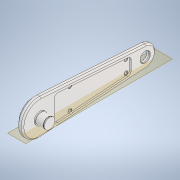
# Autodesk Inventor part: 1.3_2_SideArmClose
Saved by Autodesk Inventor 2021 (Build 250183000, 183)
## iProperties
Created: 2025-11-12
Part Number: 1.3_2_SideArmClose
Material: ABS Plastic
Document SubType Name: Modeling
Designer: Admin
Density: 1.06 g/cm^3
Appearance: Smooth - White
Mass: 286.641 g
Surface Area: 768.971 cm^2
Volume: 270.416 cm^3
Author: Admin
Title: Side Arm Closure (3rd)
Autodesk Inventor part; units mm, degrees
ref_plane "YZ Plane" through (0, 0, 0) normal (1, 0, 0) x (0, 1, 0)
ref_plane "XY Plane" through (0, 0, 0) normal (0, 0, 1) x (1, 0, 0)
sketch "Sketch1" plane through (0, 0, 0) normal (1, 0, 0) x (0, 1, 0)
  circle A0 centre (0, 0) radius 50
  circle A1 centre (0, -300) radius 30
  line L0 (0, 0) -> (0, -300) construction
  line L1 (49.8888, -3.3333) -> (29.9333, -302)
  line L2 (-49.8888, -3.3333) -> (-29.9333, -302)
  dimension "d0" = 300
  dimension "d1" = 100
  dimension "d2" = 60
  constraints: 6 end point, 4 point on circle, 3 tangent, 2 centre point, 1 coincident, 1 equal length, 1 vertical
  measures "d0" distance of L0.start L0.end
  measures "d1" diameter of A0
  measures "d2" diameter of A1
extrude "Extrusion1" add sketch "Sketch1" along normal blind 11
sketch "Sketch2" plane through (0, 0, 0) normal (0, 1, 0) x (-1, 0, 0)
  line L0 (0, 0) -> (0, 42.5)
  line L1 (0, 50) -> (0, -3.3333) projected
  line L2 (0, 42.5) -> (1, 42.5)
  line L3 (1, 42.5) -> (1, 40)
  line L4 (1, 40) -> (10, 40)
  line L5 (10, 40) -> (10, 0)
  line L6 (10, 0) -> (0, 0)
  dimension "d7" = 40
  dimension "d8" = 10
  dimension "d9" = 1
  dimension "d68" = 42.5
  constraints: 12 end point, 5 perpendicular, 1 collinear
  measures "d7" distance of L4.end L5.end
  measures "d8" distance between parallel lines of L0 L5
  measures "d9" distance of L0.end L2.end
  measures "d68" distance between parallel lines of L6 L2
revolve "Revolution1" add sketch "Sketch2" angle 360 about axis through (-10, 0, 0) along (1, 0, 0)
sketch "Sketch3" plane through (0, 0, 0) normal (0, 1, 0) x (-1, 0, 0)
  line L0 (10, -40) -> (10, 40) projected
  line L1 (10, -30) -> (-2, -30)
  line L2 (-2, -30) -> (-2, -12)
  line L3 (-2, -12) -> (-5, -12)
  line L4 (-5, -12) -> (-5, -10)
  line L5 (-5, -10) -> (-11, -10)
  line L6 (-11, -10) -> (-11, 0)
  line L7 (-11, 50) -> (-11, -3.3333) projected
  line L8 (-11, 0) -> (10, 0)
  line L9 (10, 0) -> (10, -30)
  line L10 (14.2, 0) -> (-15.2, 0) projected
  point P0 (0, 0)
  point P1 (10, 0)
  dimension "d11" = 30
  dimension "d12" = 12
  dimension "d13" = 6
  dimension "d14" = 3
  dimension "d15" = 12
  dimension "d16" = 10
  constraints: 16 end point, 6 perpendicular, 2 point on line, 1 collinear, 1 horizontal
  measures "d11" distance between parallel lines of L8 L1
  measures "d12" distance of L1.start L1.end
  measures "d13" distance of L4.end L5.end
  measures "d14" distance of L2.end L3.end
  measures "d15" distance between parallel lines of L8 L3
  measures "d16" distance between parallel lines of L8 L5
revolve "Revolution2" cut sketch "Sketch3" angle 360 about axis through (-10, 0, 0) along (1, 0, 0)
sketch "Sketch4" plane through (2, 0, 0) normal (-1, 0, 0) x (0, 0, 1)
  line L0 (-16.2635, -16.2635) -> (16.2635, -16.2635)
  line L1 (16.2635, -16.2635) -> (16.2635, 16.2635)
  line L2 (16.2635, 16.2635) -> (-16.2635, 16.2635)
  line L3 (-16.2635, 16.2635) -> (-16.2635, -16.2635)
  line L4 (-16.2635, -16.2635) -> (16.2635, 16.2635) construction
  line L5 (16.2635, -16.2635) -> (-16.2635, 16.2635) construction
  circle A0 centre (0, 0) radius 23
  dimension "d18" = 46
  constraints: 12 end point, 5 coincident, 2 midpoint, 2 parallel, 2 perpendicular, 1 horizontal, 3 other
hole "Hole1" [suppressed]
sketch "Sketch5" plane through (0, 0, 0) normal (0, 1, 0) x (-1, 0, 0)
  line L0 (0, -300) -> (-11, -300)
  line L1 (0, -300) -> (-11, -300)
  line L2 (-11, -300) -> (-11, -314)
  line L3 (-11, -314) -> (-7, -314)
  line L4 (-7, -314) -> (-7, -315)
  line L5 (-7, -315) -> (0, -315)
  line L6 (0, -315) -> (0, -300)
  line L7 (-11, -3.3333) -> (-11, -302) projected
  line L8 (0, -406) -> (0, 126) projected
  point P0 (0, 0)
  dimension "d26" = 15
  dimension "d28" = 7
  dimension "d66" = 14
  dimension "d70" = 300
  constraints: 14 end point, 5 perpendicular, 2 collinear
  measures "d26" distance between parallel lines of L0 L5
  measures "d28" distance of L4.end L5.end
  measures "d66" distance between parallel lines of L0 L3
  measures "d70" distance of L0.start point (0, 0)
revolve "Revolution3" cut sketch "Sketch5" angle 360 about axis through (0, 0, -300) along (1, 0, 0)
sketch "Sketch6" plane through (11, 0, 0) normal (1, 0, 0) x (0, 0, -1)
  point P0 (0, 0)
sketch "Sketch7" plane through (0, 0, 0) normal (0, 1, 0) x (-1, 0, 0)
  line L0 (-11, -10) -> (-11, 10) projected
  line L1 (-11, 0) -> (-11, -17)
  line L2 (-11, -17) -> (-14, -17)
  line L3 (-14, -17) -> (-14, -15)
  line L4 (-14, -15) -> (-35, -15)
  line L5 (-35, -15) -> (-35, -14.3)
  line L6 (-35, -14.3) -> (-36.6, -14.3)
  line L7 (-36.6, -14.3) -> (-36.6, -15)
  line L8 (-36.6, -15) -> (-38.7, -15)
  line L9 (-38.7, -15) -> (-38.7, 0)
  line L10 (-38.7, 0) -> (-11, 0)
  point P0 (0, 0)
  dimension "d30" = 15
  dimension "d31" = 17
  dimension "d33" = 1.6
  dimension "d34" = 2.1
  dimension "d35" = 21
  dimension "d36" = 3
  dimension "d65" = 14.3
  constraints: 20 end point, 8 perpendicular, 2 vertical, 1 collinear, 1 midpoint
  measures "d30" distance between parallel lines of L10 L8
  measures "d31" distance between parallel lines of L10 L2
  measures "d33" distance of L5.end L6.end
  measures "d34" distance of L7.end L8.end
  measures "d35" distance of L3.end L4.end
  measures "d36" distance of L1.end L2.end
  measures "d65" distance between parallel lines of L10 L6
revolve "Revolution4" add sketch "Sketch7" angle 360 about axis through (38.7, 0, 0) along (-1, 0, 0)
sketch "Sketch8" plane through (11, 0, 0) normal (1, 0, 0) x (0, 0, -1)
  line L0 (260, -22.7172) -> (260, 22.7172)
  line L1 (260, 22.7172) -> (40, 37.4166)
  line L2 (40, 37.4166) -> (40, -37.4166)
  line L3 (40, -37.4166) -> (260, -22.7172)
  line L4 (3.3333, -49.8888) -> (302, -29.9333) projected
  line L5 (302, 29.9333) -> (3.3333, 49.8888) projected
  circle A0 centre (300, 0) radius 14 projected
  circle A1 centre (0, 0) radius 10 projected
  dimension "d39" = 40
  dimension "d40" = 40
  dimension "d41" = 10
  dimension "d42" = 10
  constraints: 8 end point, 3 parallel, 2 coincident, 1 vertical
  measures "d39" distance from line of point (0, 0) L2
  measures "d40" distance from line of point (300, 0) L0
  measures "d41" distance between parallel lines of L4 L3
  measures "d42" distance between parallel lines of L5 L1
extrude "Extrusion2" cut sketch "Sketch8" against normal blind 5 contours L3 L2 L1 L0
fillet "Fillet1" radius 10 4 edges at (8.5, 37.4166, -40) (8.5, -37.4166, -40) (8.5, -22.7172, -260) (8.5, 22.7172, -260)
chamfer "Chamfer1" distance 4 angle 45 4 edges at (11, 39.911, -152.6667) (11, 0, 50) (11, -39.911, -152.6667) (11, 0, -330)
sketch "Sketch9" plane through (11, 0, 0) normal (1, 0, 0) x (0, 0, -1)
  line L0 (-126, 0) -> (406, 0) projected
  line L1 (0, -70) -> (0, 70) projected
  circle A0 centre (300, 0) radius 14 projected
  point P0 (0, 0)
  point P1 (250, -17)
  point P2 (90, -30)
  point P3 (250, 17)
  point P4 (90, 30)
  dimension "d49" = 17
  dimension "d50" = 30
  dimension "d51" = 90
  dimension "d52" = 50
  constraints: 2 symmetric about line, 1 coincident
  measures "d49" distance from line of L0 point (250, -17)
  measures "d50" distance from line of L0 point (90, -30)
  measures "d51" distance from line of point (90, -30) L1
  measures "d52" horizontal distance of point (250, -17) point (300, 0)
hole "Hole2" at (11, -30, -90) at (11, -17, -250) at (11, 17, -250) at (11, 30, -90) direction (-1, 0, 0) diameter 6.6 end through all counterbore diameter 11 counterbore depth 6 clearance for "Hex Head Cap Screw ISO 24017" size "M6" standard "ISO"
ref_plane "Work Plane1" through (24.5, -15, 0) normal (0, 1, 0) x (-1, 0, 0)
sketch "Sketch10" plane through (24.5, -15, 0) normal (0, 1, 0) x (-1, 0, 0)
  line L0 (5, 0) -> (-5, 0) construction
  line L1 (5, 4) -> (-5, 4)
  line L2 (-5, -4) -> (5, -4)
  arc A0 (5, -4) -> (5, 4) centre (5, 0) ccw
  arc A1 (-5, 4) -> (-5, -4) centre (-5, 0) ccw
  line L3 (10.5, 17) -> (10.5, -17) projected
  point P0 (24.5, 0)
  point P1 (0, 0)
  point P2 (10.5, 0)
  dimension "d60" = 8
  dimension "d61" = 10
  dimension "d62" = 10.5
  constraints: 8 end point, 4 point on circle, 4 tangent, 2 centre point, 2 midpoint, 1 horizontal, 1 parallel, 1 point on line
  measures "d60" distance between parallel lines of L2 L1
  measures "d61" distance of L0.end L0.start
  measures "d62" distance from line of L3 point (0, 0)
extrude "Extrusion3" [suppressed]
fillet "Fillet2" radius 0.3 1 edges at (7, 0, -285)
fillet "Fillet3" radius 0.5 1 edges at (-1, 0, -40)
chamfer "Chamfer2" distance 1 angle 45 3 edges at (-10, 0, -40) (0, 0, -285) (11, 0, -286)
body "Solid1"
